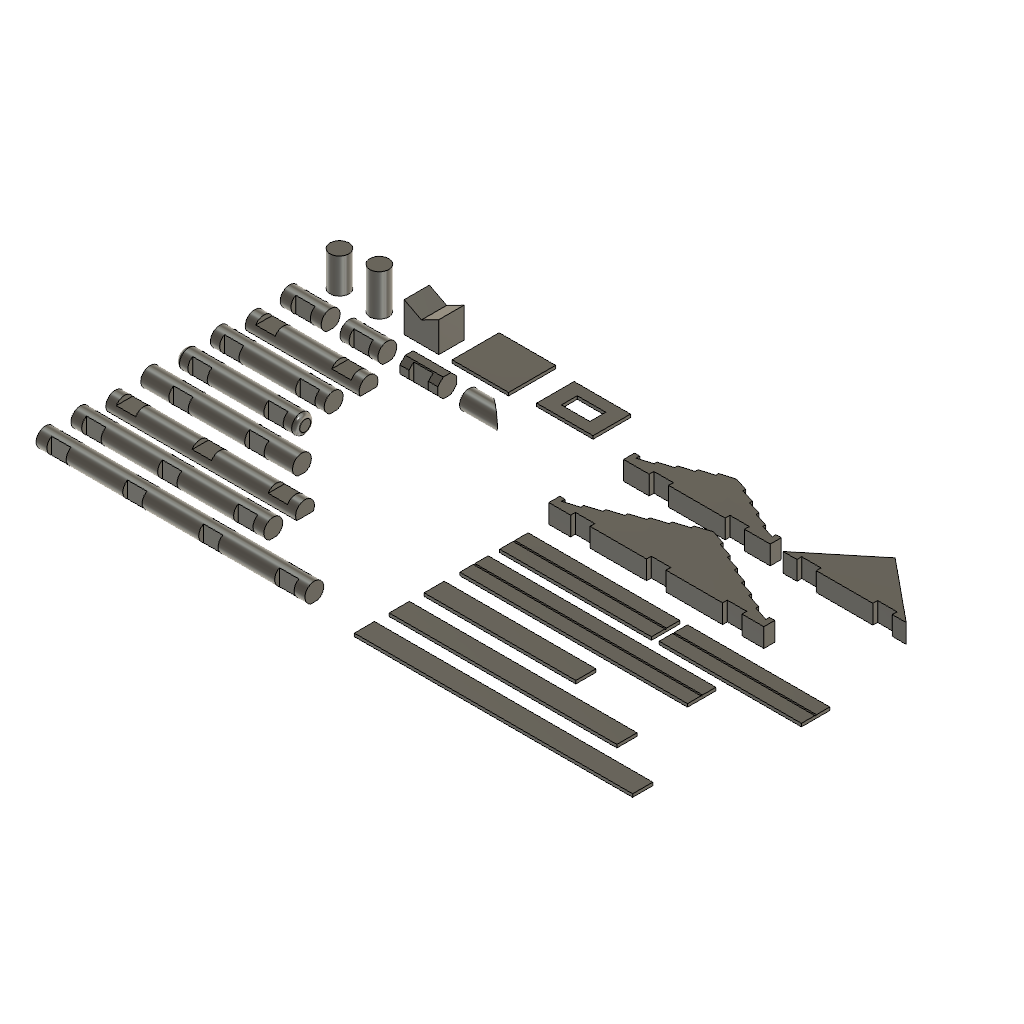
lincoln_logs (Autodesk Fusion 360 design; units mm, degrees)
part number: 2026-11-10-09-19-09-464
part number: 2026-11-10-09-19-09-786
part number: 2026-11-10-09-19-09-864
part number: 2026-11-10-09-19-09-945
part number: 2026-11-10-09-19-10-058
part number: 2026-11-10-09-19-10-167
part number: 2026-11-10-09-19-10-289
part number: 2026-11-10-09-19-10-433
part number: 2026-11-10-09-19-10-590
part number: 2026-11-10-09-19-10-777
part number: 2026-11-10-09-19-10-901
part number: 2026-11-10-09-19-11-031
part number: 2026-11-10-09-19-11-149
part number: 2026-11-10-09-19-11-184
part number: 2026-11-10-09-19-11-255
part number: 2026-11-10-09-19-11-618
part number: 2026-11-10-09-19-12-021
part number: 2026-11-10-09-19-12-238
part number: 2026-11-10-09-19-12-344
part number: 2026-11-10-09-19-12-451
part number: 2026-11-10-09-19-12-561
part number: 2026-11-10-09-19-12-786
part number: 2026-11-10-09-19-13-022
part number: 2026-11-10-09-19-13-284
part number: 2026-11-10-09-19-13-795
part number: 2026-11-10-09-19-13-962
Autodesk Fusion 360 part; units mm, degrees
(part 1 of 2)
sketch "Section" plane through (0, 0, 0) normal (1, 0, 0) x (0, 0, -1) in component "log_1insert_1-5_8"
  circle A0 centre (-8.725, 0) radius 9.525
  line L0 (0, -3.821) -> (0, 3.821)
  dimension "d20" = 8.725
  dimension "d21" = 19.05
  constraint horizontal origin A0.centre
  constraint coincident A0 L0.start
  constraint coincident A0 L0.end
  constraint coincident origin L0
  constraint vertical L0
  measures "d20" horizontal distance of origin A0.centre
  measures "d21" diameter of A0
extrude "Log" add sketch "Section" along normal blind 41.275 contours A0 L0 picked at (-13.348, 0.8095) makes body 1 in component "log_1insert_1-5_8"
sketch "Notch" plane through (0, 0, 0) normal (0, 0, 1) x (1, 0, 0) in component "log_1insert_1-5_8"
  line L0 (10.9125, 4.7625) -> (30.3625, 4.7625)
  line L1 (30.3625, 4.7625) -> (30.3625, 10.525)
  line L2 (30.3625, 10.525) -> (10.9125, 10.525)
  line L3 (10.9125, 10.525) -> (10.9125, 4.7625)
  line L4 (10.9125, -4.7625) -> (30.3625, -4.7625)
  line L5 (30.3625, -4.7625) -> (30.3625, -10.525)
  line L6 (30.3625, -10.525) -> (10.9125, -10.525)
  line L7 (10.9125, -10.525) -> (10.9125, -4.7625)
  dimension "d24" = 10.9125
  dimension "d25" = 4.7625
  dimension "d26" = 30.3625
  dimension "d27" = 10.525
  dimension "d28" = 10.9125
  dimension "d29" = 4.7625
  dimension "d30" = 30.3625
  dimension "d31" = 10.525
  constraint horizontal L0
  constraint vertical L1
  constraint horizontal L2
  constraint vertical L3
  constraint horizontal L4
  constraint vertical L5
  constraint horizontal L6
  constraint vertical L7
  measures "d24" horizontal distance of origin L0.start
  measures "d25" vertical distance of origin L0.start
  measures "d26" horizontal distance of origin L1.end
  measures "d27" vertical distance of origin L1.end
  measures "d28" horizontal distance of origin L4.start
  measures "d29" vertical distance of origin L4.start
  measures "d30" horizontal distance of origin L5.end
  measures "d31" vertical distance of origin L5.end
extrude "Notch cut" cut sketch "Notch" along normal blind 19.05 bodies 1 in component "log_1insert_1-5_8"
pattern_linear "Notch pattern" count 2 spacing 0.001 along (1, 0, 0) count 3 spacing 0 along (1, 0, 0) of "Notch cut" in component "log_1insert_1-5_8"
sketch "Section (2)" plane through (0, 0, 0) normal (1, 0, 0) x (0, 0, -1) in component "log_1insert_1-1_2_round"
  circle A0 centre (-8.725, 0) radius 9.525
  line L0 (0, -3.821) -> (0, 3.821)
  dimension "d42" = 8.725
  dimension "d43" = 19.05
  constraint horizontal origin A0.centre
  constraint coincident A0 L0.start
  constraint coincident A0 L0.end
  constraint coincident origin L0
  constraint vertical L0
  measures "d42" horizontal distance of origin A0.centre
  measures "d43" diameter of A0
extrude "Log'" add sketch "Section (2)" along normal blind 38.1 separate body contours A0 L0 picked at (-13.348, 0.8095) makes body 2 in component "log_1insert_1-1_2_round"
sketch "Notch (2)" plane through (0, 0, 0) normal (0, 0, 1) x (1, 0, 0) in component "log_1insert_1-1_2_round"
  line L0 (9.325, 4.7625) -> (28.775, 4.7625)
  line L1 (28.775, 4.7625) -> (28.775, 10.525)
  line L2 (28.775, 10.525) -> (9.325, 10.525)
  line L3 (9.325, 10.525) -> (9.325, 4.7625)
  line L4 (9.325, -4.7625) -> (28.775, -4.7625)
  line L5 (28.775, -4.7625) -> (28.775, -10.525)
  line L6 (28.775, -10.525) -> (9.325, -10.525)
  line L7 (9.325, -10.525) -> (9.325, -4.7625)
  dimension "d46" = 9.325
  dimension "d47" = 4.7625
  dimension "d48" = 28.775
  dimension "d49" = 10.525
  dimension "d50" = 9.325
  dimension "d51" = 4.7625
  dimension "d52" = 28.775
  dimension "d53" = 10.525
  constraint horizontal L0
  constraint vertical L1
  constraint horizontal L2
  constraint vertical L3
  constraint horizontal L4
  constraint vertical L5
  constraint horizontal L6
  constraint vertical L7
  measures "d46" horizontal distance of origin L0.start
  measures "d47" vertical distance of origin L0.start
  measures "d48" horizontal distance of origin L1.end
  measures "d49" vertical distance of origin L1.end
  measures "d50" horizontal distance of origin L4.start
  measures "d51" vertical distance of origin L4.start
  measures "d52" horizontal distance of origin L5.end
  measures "d53" vertical distance of origin L5.end
extrude "Notch cut'" cut sketch "Notch (2)" along normal blind 19.05 bodies 2 in component "log_1insert_1-1_2_round"
pattern_linear "Notch pattern'" count 2 spacing 0.001 along (1, 0, 0) count 3 spacing 0 along (1, 0, 0) of "Notch cut'" in component "log_1insert_1-1_2_round"
sketch "Section (3)" plane through (0, 0, 0) normal (1, 0, 0) x (0, 0, -1) in component "log_1insert_1-1_2_octagonal"
  line L0 (0, -9.525) -> (0, 9.525)
  line L1 (0, 9.525) -> (-19.05, 9.525)
  line L2 (-19.05, 9.525) -> (-19.05, -9.525)
  line L3 (-19.05, -9.525) -> (0, -9.525)
  dimension "d64" = 9.525
  dimension "d65" = 9.525
  dimension "d66" = 19.05
  constraint vertical L0
  constraint horizontal L1
  constraint vertical L2
  constraint horizontal L3
  constraint vertical origin L0.start
  measures "d64" vertical distance of origin L0.start
  measures "d65" vertical distance of origin L1.end
  measures "d66" horizontal distance of origin L1.end
extrude "Log''" add sketch "Section (3)" along normal blind 38.1 separate body makes body 3 in component "log_1insert_1-1_2_octagonal"
chamfer "Octagon corners" distance 5.5796 angle 45 4 edges at (19.05, -9.525, 19.05) (19.05, 9.525, 19.05) (19.05, 9.525, 0) (19.05, -9.525, 0) tangent chain off on bodies 3 in component "log_1insert_1-1_2_octagonal"
sketch "Notch (3)" plane through (0, 0, 0) normal (0, 0, 1) x (1, 0, 0) in component "log_1insert_1-1_2_octagonal"
  line L0 (9.325, 4.7625) -> (28.775, 4.7625)
  line L1 (28.775, 4.7625) -> (28.775, 10.525)
  line L2 (28.775, 10.525) -> (9.325, 10.525)
  line L3 (9.325, 10.525) -> (9.325, 4.7625)
  line L4 (9.325, -4.7625) -> (28.775, -4.7625)
  line L5 (28.775, -4.7625) -> (28.775, -10.525)
  line L6 (28.775, -10.525) -> (9.325, -10.525)
  line L7 (9.325, -10.525) -> (9.325, -4.7625)
  dimension "d70" = 9.325
  dimension "d71" = 4.7625
  dimension "d72" = 28.775
  dimension "d73" = 10.525
  dimension "d74" = 9.325
  dimension "d75" = 4.7625
  dimension "d76" = 28.775
  dimension "d77" = 10.525
  constraint horizontal L0
  constraint vertical L1
  constraint horizontal L2
  constraint vertical L3
  constraint horizontal L4
  constraint vertical L5
  constraint horizontal L6
  constraint vertical L7
  measures "d70" horizontal distance of origin L0.start
  measures "d71" vertical distance of origin L0.start
  measures "d72" horizontal distance of origin L1.end
  measures "d73" vertical distance of origin L1.end
  measures "d74" horizontal distance of origin L4.start
  measures "d75" vertical distance of origin L4.start
  measures "d76" horizontal distance of origin L5.end
  measures "d77" vertical distance of origin L5.end
extrude "Notch cut''" cut sketch "Notch (3)" along normal blind 19.05 bodies 3 in component "log_1insert_1-1_2_octagonal"
pattern_linear "Notch pattern''" count 2 spacing 0.001 along (1, 0, 0) count 3 spacing 0 along (1, 0, 0) of "Notch cut''" in component "log_1insert_1-1_2_octagonal"
sketch "Section (4)" plane through (0, 0, 0) normal (1, 0, 0) x (0, 0, -1) in component "log_2insert_4-1_2"
  circle A0 centre (-8.725, 0) radius 9.525
  line L0 (0, -3.821) -> (0, 3.821)
  dimension "d88" = 8.725
  dimension "d89" = 19.05
  constraint horizontal origin A0.centre
  constraint coincident A0 L0.start
  constraint coincident A0 L0.end
  constraint coincident origin L0
  constraint vertical L0
  measures "d88" horizontal distance of origin A0.centre
  measures "d89" diameter of A0
extrude "Log'''" add sketch "Section (4)" along normal blind 114.3 separate body contours A0 L0 picked at (-13.348, 0.8095) makes body 4 in component "log_2insert_4-1_2"
sketch "Notch (4)" plane through (0, 0, 0) normal (0, 0, 1) x (1, 0, 0) in component "log_2insert_4-1_2"
  line L0 (9.325, 4.7625) -> (28.775, 4.7625)
  line L1 (28.775, 4.7625) -> (28.775, 10.525)
  line L2 (28.775, 10.525) -> (9.325, 10.525)
  line L3 (9.325, 10.525) -> (9.325, 4.7625)
  line L4 (9.325, -4.7625) -> (28.775, -4.7625)
  line L5 (28.775, -4.7625) -> (28.775, -10.525)
  line L6 (28.775, -10.525) -> (9.325, -10.525)
  line L7 (9.325, -10.525) -> (9.325, -4.7625)
  dimension "d92" = 9.325
  dimension "d93" = 4.7625
  dimension "d94" = 28.775
  dimension "d95" = 10.525
  dimension "d96" = 9.325
  dimension "d97" = 4.7625
  dimension "d98" = 28.775
  dimension "d99" = 10.525
  constraint horizontal L0
  constraint vertical L1
  constraint horizontal L2
  constraint vertical L3
  constraint horizontal L4
  constraint vertical L5
  constraint horizontal L6
  constraint vertical L7
  measures "d92" horizontal distance of origin L0.start
  measures "d93" vertical distance of origin L0.start
  measures "d94" horizontal distance of origin L1.end
  measures "d95" vertical distance of origin L1.end
  measures "d96" horizontal distance of origin L4.start
  measures "d97" vertical distance of origin L4.start
  measures "d98" horizontal distance of origin L5.end
  measures "d99" vertical distance of origin L5.end
extrude "Notch cut'''" cut sketch "Notch (4)" along normal blind 19.05 bodies 4 in component "log_2insert_4-1_2"
pattern_linear "Notch pattern'''" count 2 spacing 76.2 along (1, 0, 0) count 3 spacing 0 along (1, 0, 0) of "Notch cut'''" in component "log_2insert_4-1_2"
sketch "Section (5)" plane through (0, 0, 0) normal (1, 0, 0) x (0, 0, -1) in component "log_2insert_6"
  circle A0 centre (-8.725, 0) radius 9.525
  line L0 (0, -3.821) -> (0, 3.821)
  dimension "d110" = 8.725
  dimension "d111" = 19.05
  constraint horizontal origin A0.centre
  constraint coincident A0 L0.start
  constraint coincident A0 L0.end
  constraint coincident origin L0
  constraint vertical L0
  measures "d110" horizontal distance of origin A0.centre
  measures "d111" diameter of A0
extrude "Log''''" add sketch "Section (5)" along normal blind 152.4 separate body contours A0 L0 picked at (-13.348, 0.8095) makes body 5 in component "log_2insert_6"
sketch "Notch (5)" plane through (0, 0, 0) normal (0, 0, 1) x (1, 0, 0) in component "log_2insert_6"
  line L0 (28.375, 4.7625) -> (47.825, 4.7625)
  line L1 (47.825, 4.7625) -> (47.825, 10.525)
  line L2 (47.825, 10.525) -> (28.375, 10.525)
  line L3 (28.375, 10.525) -> (28.375, 4.7625)
  line L4 (28.375, -4.7625) -> (47.825, -4.7625)
  line L5 (47.825, -4.7625) -> (47.825, -10.525)
  line L6 (47.825, -10.525) -> (28.375, -10.525)
  line L7 (28.375, -10.525) -> (28.375, -4.7625)
  dimension "d114" = 28.375
  dimension "d115" = 4.7625
  dimension "d116" = 47.825
  dimension "d117" = 10.525
  dimension "d118" = 28.375
  dimension "d119" = 4.7625
  dimension "d120" = 47.825
  dimension "d121" = 10.525
  constraint horizontal L0
  constraint vertical L1
  constraint horizontal L2
  constraint vertical L3
  constraint horizontal L4
  constraint vertical L5
  constraint horizontal L6
  constraint vertical L7
  measures "d114" horizontal distance of origin L0.start
  measures "d115" vertical distance of origin L0.start
  measures "d116" horizontal distance of origin L1.end
  measures "d117" vertical distance of origin L1.end
  measures "d118" horizontal distance of origin L4.start
  measures "d119" vertical distance of origin L4.start
  measures "d120" horizontal distance of origin L5.end
  measures "d121" vertical distance of origin L5.end
extrude "Notch cut''''" cut sketch "Notch (5)" along normal blind 19.05 bodies 5 in component "log_2insert_6"
pattern_linear "Notch pattern''''" count 2 spacing 76.2 along (1, 0, 0) count 3 spacing 0 along (1, 0, 0) of "Notch cut''''" in component "log_2insert_6"
sketch "Section (6)" plane through (0, 0, 0) normal (1, 0, 0) x (0, 0, -1) in component "log_3insert_7-5_8"
  circle A0 centre (-8.725, 0) radius 9.525
  line L0 (0, -3.821) -> (0, 3.821)
  dimension "d132" = 8.725
  dimension "d133" = 19.05
  constraint horizontal origin A0.centre
  constraint coincident A0 L0.start
  constraint coincident A0 L0.end
  constraint coincident origin L0
  constraint vertical L0
  measures "d132" horizontal distance of origin A0.centre
  measures "d133" diameter of A0
extrude "Log'''''" add sketch "Section (6)" along normal blind 193.675 separate body contours A0 L0 picked at (-13.348, 0.8095) makes body 6 in component "log_3insert_7-5_8"
sketch "Notch (6)" plane through (0, 0, 0) normal (0, 0, 1) x (1, 0, 0) in component "log_3insert_7-5_8"
  line L0 (10.9125, 4.7625) -> (30.3625, 4.7625)
  line L1 (30.3625, 4.7625) -> (30.3625, 10.525)
  line L2 (30.3625, 10.525) -> (10.9125, 10.525)
  line L3 (10.9125, 10.525) -> (10.9125, 4.7625)
  line L4 (10.9125, -4.7625) -> (30.3625, -4.7625)
  line L5 (30.3625, -4.7625) -> (30.3625, -10.525)
  line L6 (30.3625, -10.525) -> (10.9125, -10.525)
  line L7 (10.9125, -10.525) -> (10.9125, -4.7625)
  dimension "d136" = 10.9125
  dimension "d137" = 4.7625
  dimension "d138" = 30.3625
  dimension "d139" = 10.525
  dimension "d140" = 10.9125
  dimension "d141" = 4.7625
  dimension "d142" = 30.3625
  dimension "d143" = 10.525
  constraint horizontal L0
  constraint vertical L1
  constraint horizontal L2
  constraint vertical L3
  constraint horizontal L4
  constraint vertical L5
  constraint horizontal L6
  constraint vertical L7
  measures "d136" horizontal distance of origin L0.start
  measures "d137" vertical distance of origin L0.start
  measures "d138" horizontal distance of origin L1.end
  measures "d139" vertical distance of origin L1.end
  measures "d140" horizontal distance of origin L4.start
  measures "d141" vertical distance of origin L4.start
  measures "d142" horizontal distance of origin L5.end
  measures "d143" vertical distance of origin L5.end
extrude "Notch cut'''''" cut sketch "Notch (6)" along normal blind 19.05 bodies 6 in component "log_3insert_7-5_8"
pattern_linear "Notch pattern'''''" count 3 spacing 76.2 along (1, 0, 0) count 3 spacing 0 along (1, 0, 0) of "Notch cut'''''" in component "log_3insert_7-5_8"
sketch "Section (7)" plane through (0, 0, 0) normal (1, 0, 0) x (0, 0, -1) in component "log_4insert_10-5_8"
  circle A0 centre (-8.725, 0) radius 9.525
  line L0 (0, -3.821) -> (0, 3.821)
  dimension "d154" = 8.725
  dimension "d155" = 19.05
  constraint horizontal origin A0.centre
  constraint coincident A0 L0.start
  constraint coincident A0 L0.end
  constraint coincident origin L0
  constraint vertical L0
  measures "d154" horizontal distance of origin A0.centre
  measures "d155" diameter of A0
extrude "Log''''''" add sketch "Section (7)" along normal blind 269.875 separate body contours A0 L0 picked at (-13.348, 0.8095) makes body 7 in component "log_4insert_10-5_8"
sketch "Notch (7)" plane through (0, 0, 0) normal (0, 0, 1) x (1, 0, 0) in component "log_4insert_10-5_8"
  line L0 (10.9125, 4.7625) -> (30.3625, 4.7625)
  line L1 (30.3625, 4.7625) -> (30.3625, 10.525)
  line L2 (30.3625, 10.525) -> (10.9125, 10.525)
  line L3 (10.9125, 10.525) -> (10.9125, 4.7625)
  line L4 (10.9125, -4.7625) -> (30.3625, -4.7625)
  line L5 (30.3625, -4.7625) -> (30.3625, -10.525)
  line L6 (30.3625, -10.525) -> (10.9125, -10.525)
  line L7 (10.9125, -10.525) -> (10.9125, -4.7625)
  dimension "d158" = 10.9125
  dimension "d159" = 4.7625
  dimension "d160" = 30.3625
  dimension "d161" = 10.525
  dimension "d162" = 10.9125
  dimension "d163" = 4.7625
  dimension "d164" = 30.3625
  dimension "d165" = 10.525
  constraint horizontal L0
  constraint vertical L1
  constraint horizontal L2
  constraint vertical L3
  constraint horizontal L4
  constraint vertical L5
  constraint horizontal L6
  constraint vertical L7
  measures "d158" horizontal distance of origin L0.start
  measures "d159" vertical distance of origin L0.start
  measures "d160" horizontal distance of origin L1.end
  measures "d161" vertical distance of origin L1.end
  measures "d162" horizontal distance of origin L4.start
  measures "d163" vertical distance of origin L4.start
  measures "d164" horizontal distance of origin L5.end
  measures "d165" vertical distance of origin L5.end
extrude "Notch cut''''''" cut sketch "Notch (7)" along normal blind 19.05 bodies 7 in component "log_4insert_10-5_8"
pattern_linear "Notch pattern''''''" count 4 spacing 76.2 along (1, 0, 0) count 3 spacing 0 along (1, 0, 0) of "Notch cut''''''" in component "log_4insert_10-5_8"
sketch "Section (8)" plane through (0, 0, 0) normal (1, 0, 0) x (0, 0, -1) in component "beveled_end_4-3_4"
  circle A0 centre (-8.725, 0) radius 9.525
  line L0 (0, -3.821) -> (0, 3.821)
  dimension "d176" = 8.725
  dimension "d177" = 19.05
  constraint horizontal origin A0.centre
  constraint coincident A0 L0.start
  constraint coincident A0 L0.end
  constraint coincident origin L0
  constraint vertical L0
  measures "d176" horizontal distance of origin A0.centre
  measures "d177" diameter of A0
extrude "Log'''''''" add sketch "Section (8)" along normal blind 120.65 separate body makes body 8 in component "beveled_end_4-3_4"
fillet "Rounded ends" radius 4 2 edges at (120.65, -3.4444, 17.6054) (0, -3.4444, 17.6054) on bodies 8 in component "beveled_end_4-3_4"
extrude "Printing flat" cut sketch "Section (8)" along normal blind 120.65 contours A0 L0 picked at (0.1472, 0.8627) bodies 8 in component "beveled_end_4-3_4"
sketch "Notch (8)" plane through (0, 0, 0) normal (0, 0, 1) x (1, 0, 0) in component "beveled_end_4-3_4"
  line L0 (12.5, 4.7625) -> (31.95, 4.7625)
  line L1 (31.95, 4.7625) -> (31.95, 10.525)
  line L2 (31.95, 10.525) -> (12.5, 10.525)
  line L3 (12.5, 10.525) -> (12.5, 4.7625)
  line L4 (12.5, -4.7625) -> (31.95, -4.7625)
  line L5 (31.95, -4.7625) -> (31.95, -10.525)
  line L6 (31.95, -10.525) -> (12.5, -10.525)
  line L7 (12.5, -10.525) -> (12.5, -4.7625)
  dimension "d185" = 12.5
  dimension "d186" = 4.7625
  dimension "d187" = 31.95
  dimension "d188" = 10.525
  dimension "d189" = 12.5
  dimension "d190" = 4.7625
  dimension "d191" = 31.95
  dimension "d192" = 10.525
  constraint horizontal L0
  constraint vertical L1
  constraint horizontal L2
  constraint vertical L3
  constraint horizontal L4
  constraint vertical L5
  constraint horizontal L6
  constraint vertical L7
  measures "d185" horizontal distance of origin L0.start
  measures "d186" vertical distance of origin L0.start
  measures "d187" horizontal distance of origin L1.end
  measures "d188" vertical distance of origin L1.end
  measures "d189" horizontal distance of origin L4.start
  measures "d190" vertical distance of origin L4.start
  measures "d191" horizontal distance of origin L5.end
  measures "d192" vertical distance of origin L5.end
extrude "Notch cut'''''''" cut sketch "Notch (8)" along normal blind 19.05 bodies 8 in component "beveled_end_4-3_4"
pattern_linear "Notch pattern'''''''" count 2 spacing 76.2 along (1, 0, 0) count 3 spacing 0 along (1, 0, 0) of "Notch cut'''''''" in component "beveled_end_4-3_4"
sketch "Section (9)" plane through (0, 0, 0) normal (1, 0, 0) x (0, 0, -1) in component "half_log_4-1_2"
  circle A0 centre (-4.7625, 0) radius 9.525
  line L0 (0, -8.2489) -> (0, 8.2489)
  dimension "d203" = 4.7625
  dimension "d204" = 19.05
  constraint horizontal origin A0.centre
  constraint coincident A0 L0.start
  constraint coincident A0 L0.end
  constraint coincident origin L0
  constraint vertical L0
  measures "d203" horizontal distance of origin A0.centre
  measures "d204" diameter of A0
extrude "Log''''''''" add sketch "Section (9)" along normal blind 114.3 separate body contours A0 L0 picked at (-7.0899, 2.1595) makes body 9 in component "half_log_4-1_2"
sketch "Notch (9)" plane through (0, 0, 0) normal (0, 1, 0) x (1, 0, 0) in component "half_log_4-1_2"
  line L0 (9.325, -9.525) -> (28.775, -9.525)
  line L1 (28.775, -9.525) -> (28.775, -15.2875)
  line L2 (28.775, -15.2875) -> (9.325, -15.2875)
  line L3 (9.325, -15.2875) -> (9.325, -9.525)
  dimension "d207" = 9.325
  dimension "d208" = 9.525
  dimension "d209" = 28.775
  dimension "d210" = 15.2875
  constraint horizontal L0
  constraint vertical L1
  constraint horizontal L2
  constraint vertical L3
  measures "d207" horizontal distance of origin L0.start
  measures "d208" vertical distance of origin L0.start
  measures "d209" horizontal distance of origin L1.end
  measures "d210" vertical distance of origin L1.end
extrude "Notch cut''''''''" cut sketch "Notch (9)" along normal mid plane 21.05 bodies 9 in component "half_log_4-1_2"
pattern_linear "Notch pattern''''''''" count 2 spacing 76.2 along (1, 0, 0) count 3 spacing 0 along (1, 0, 0) of "Notch cut''''''''" in component "half_log_4-1_2"
sketch "Section (10)" plane through (0, 0, 0) normal (1, 0, 0) x (0, 0, -1) in component "half_log_7-1_2"
  circle A0 centre (-4.7625, 0) radius 9.525
  line L0 (0, -8.2489) -> (0, 8.2489)
  dimension "d221" = 4.7625
  dimension "d222" = 19.05
  constraint horizontal origin A0.centre
  constraint coincident A0 L0.start
  constraint coincident A0 L0.end
  constraint coincident origin L0
  constraint vertical L0
  measures "d221" horizontal distance of origin A0.centre
  measures "d222" diameter of A0
extrude "Log'''''''''" add sketch "Section (10)" along normal blind 190.5 separate body contours A0 L0 picked at (-7.0899, 2.1595) makes body 10 in component "half_log_7-1_2"
sketch "Notch (10)" plane through (0, 0, 0) normal (0, 1, 0) x (1, 0, 0) in component "half_log_7-1_2"
  line L0 (9.325, -9.525) -> (28.775, -9.525)
  line L1 (28.775, -9.525) -> (28.775, -15.2875)
  line L2 (28.775, -15.2875) -> (9.325, -15.2875)
  line L3 (9.325, -15.2875) -> (9.325, -9.525)
  dimension "d225" = 9.325
  dimension "d226" = 9.525
  dimension "d227" = 28.775
  dimension "d228" = 15.2875
  constraint horizontal L0
  constraint vertical L1
  constraint horizontal L2
  constraint vertical L3
  measures "d225" horizontal distance of origin L0.start
  measures "d226" vertical distance of origin L0.start
  measures "d227" horizontal distance of origin L1.end
  measures "d228" vertical distance of origin L1.end
extrude "Notch cut'''''''''" cut sketch "Notch (10)" along normal mid plane 21.05 bodies 10 in component "half_log_7-1_2"
pattern_linear "Notch pattern'''''''''" count 3 spacing 76.2 along (1, 0, 0) count 3 spacing 0 along (1, 0, 0) of "Notch cut'''''''''" in component "half_log_7-1_2"
sketch "Section (11)" plane through (0, 0, 0) normal (1, 0, 0) x (0, 0, -1) in component "beveled_end_1-1_2"
  circle A0 centre (-8.725, 0) radius 9.525
  line L0 (0, -3.821) -> (0, 3.821)
  dimension "d237" = 8.725
  dimension "d238" = 19.05
  constraint horizontal origin A0.centre
  constraint coincident A0 L0.start
  constraint coincident A0 L0.end
  constraint coincident origin L0
  constraint vertical L0
  measures "d237" horizontal distance of origin A0.centre
  measures "d238" diameter of A0
extrude "Log''''''''''" add sketch "Section (11)" along normal blind 38.1 separate body contours A0 L0 picked at (-13.348, 0.8095) makes body 11 in component "beveled_end_1-1_2"
sketch "Slant" plane through (0, 0, 0) normal (0, 0, 1) x (1, 0, 0) in component "beveled_end_1-1_2"
  line L0 (38.1, -9.525) -> (38.1, 9.525)
  line L1 (38.1, 9.525) -> (14.5752, 9.525)
  line L2 (14.5752, 9.525) -> (38.1, -9.525)
  dimension "d241" = 38.1
  dimension "d242" = 9.525
  dimension "d243" = 9.525
  dimension "d244" = 14.5752
  constraint vertical L0.start L0.end
  constraint horizontal L0.end L1.end
  measures "d241" horizontal distance of origin L0.start
  measures "d242" vertical distance of origin L0.start
  measures "d243" vertical distance of origin L0.end
  measures "d244" horizontal distance of origin L1.end
extrude "Slanted end" cut sketch "Slant" along normal blind 19.05 bodies 11 in component "beveled_end_1-1_2"
sketch "Section (12)" plane through (0, 0, 0) normal (0, 0, 1) x (1, 0, 0) in component "solid_log_1-3_8"
  circle A0 centre (0, 0) radius 9.525
  dimension "d248" = 19.05
  measures "d248" diameter of A0
extrude "Log'''''''''''" add sketch "Section (12)" along normal blind 34.925 separate body makes body 12 in component "solid_log_1-3_8"
sketch "Section (13)" plane through (0, 0, 0) normal (0, 0, 1) x (1, 0, 0) in component "solid_log_1-5_8"
  circle A0 centre (0, 0) radius 9.525
  dimension "d252" = 19.05
  measures "d252" diameter of A0
extrude "Log''''''''''''" add sketch "Section (13)" along normal blind 41.275 separate body makes body 13 in component "solid_log_1-5_8"
sketch "Half profile" plane through (0, 0, 0) normal (0, 0, 1) x (1, 0, 0) in component "gable_plastic_8-1_2"
  line L0 (0, 0) -> (107.95, 0)
  line L1 (107.95, 0) -> (107.95, 60.05)
  line L2 (107.95, 60.05) -> (5.4, 7.5)
  line L3 (5.4, 7.5) -> (5.4, 11.1)
  line L4 (5.4, 11.1) -> (0, 11.1)
  line L5 (0, 11.1) -> (0, 0)
  dimension "d282" = 107.95
  dimension "d283" = 60.05
  dimension "d284" = 5.4
  dimension "d285" = 7.5
  dimension "d286" = 11.1
  constraint coincident L0.start L5.end
  constraint horizontal L0.start L0.end
  constraint vertical L0.end L1.end
  constraint vertical L2.end L3.end
  constraint vertical L0.start L4.end
  constraint horizontal L3.end L4.end
  measures "d282" horizontal distance of L0.start L0.end
  measures "d283" vertical distance of L0.start L1.end
  measures "d284" horizontal distance of L0.start L2.end
  measures "d285" vertical distance of L0.start L2.end
  measures "d286" vertical distance of L0.start L3.end
extrude "Half gable" add sketch "Half profile" along normal blind 19.05 separate body makes body 14 in component "gable_plastic_8-1_2"
sketch "Step" plane through (0, 0, 0) normal (0, 0, 1) x (1, 0, 0) in component "gable_plastic_8-1_2"
  line L0 (5.4, 7.5) -> (20.05, 15.0071)
  line L1 (20.05, 15.0071) -> (20.05, 12.1071)
  line L2 (20.05, 12.1071) -> (5.4, 7.5)
  dimension "d289" = 5.4
  dimension "d290" = 7.5
  dimension "d291" = 20.05
  dimension "d292" = 15.0071
  dimension "d293" = 12.1071
  constraint vertical L0.end L1.end
  measures "d289" horizontal distance of origin L0.start
  measures "d290" vertical distance of origin L0.start
  measures "d291" horizontal distance of origin L0.end
  measures "d292" vertical distance of origin L0.end
  measures "d293" vertical distance of origin L1.end
extrude "Step cut" cut sketch "Step" along normal blind 19.05 bodies 14 in component "gable_plastic_8-1_2"
pattern_linear "Step pattern" count 7 spacing 16.4615 along (0.889957, 0.456044, 0) count 3 spacing 0 along (0.889957, 0.456044, 0) of "Step cut" in component "gable_plastic_8-1_2"
ref_plane "WorkPlane1" through (107.95, 0, 0) normal (1, 0, 0) x (0, 1, 0) in component "gable_plastic_8-1_2"
mirror "Mirror half" about plane through (107.95, 0, 0) normal (1, 0, 0) of bodies 14 merged in component "gable_plastic_8-1_2"
sketch "Notch (11)" plane through (0, 0, 0) normal (0, 0, 1) x (1, 0, 0) in component "gable_plastic_8-1_2"
  line L0 (22.025, -1) -> (41.475, -1)
  line L1 (41.475, -1) -> (41.475, 4.7625)
  line L2 (41.475, 4.7625) -> (22.025, 4.7625)
  line L3 (22.025, 4.7625) -> (22.025, -1)
  dimension "d304" = 22.025
  dimension "d305" = 1
  dimension "d306" = 41.475
  dimension "d307" = 4.7625
  constraint horizontal L0
  constraint vertical L1
  constraint horizontal L2
  constraint vertical L3
  measures "d304" horizontal distance of origin L0.start
  measures "d305" vertical distance of origin L0.start
  measures "d306" horizontal distance of origin L1.end
  measures "d307" vertical distance of origin L1.end
extrude "Notch cut''''''''''" cut sketch "Notch (11)" along normal blind 19.05 bodies 14 in component "gable_plastic_8-1_2"
pattern_linear "Notch pattern''''''''''" count 3 spacing 76.2 along (1, 0, 0) count 3 spacing 0 along (1, 0, 0) of "Notch cut''''''''''" in component "gable_plastic_8-1_2"
sketch "Half profile (2)" plane through (0, 0, 0) normal (0, 0, 1) x (1, 0, 0) in component "gable_plastic_small_2notch"
  line L0 (0, 0) -> (73.66, 0)
  line L1 (73.66, 0) -> (73.66, 42.4787)
  line L2 (73.66, 42.4787) -> (5.4, 7.5)
  line L3 (5.4, 7.5) -> (5.4, 11.1)
  line L4 (5.4, 11.1) -> (0, 11.1)
  line L5 (0, 11.1) -> (0, 0)
  dimension "d314" = 73.66
  dimension "d315" = 42.4787
  dimension "d316" = 5.4
  dimension "d317" = 7.5
  dimension "d318" = 11.1
  constraint coincident L0.start L5.end
  constraint horizontal L0.start L0.end
  constraint vertical L0.end L1.end
  constraint vertical L2.end L3.end
  constraint vertical L0.start L4.end
  constraint horizontal L3.end L4.end
  measures "d314" horizontal distance of L0.start L0.end
  measures "d315" vertical distance of L0.start L1.end
  measures "d316" horizontal distance of L0.start L2.end
  measures "d317" vertical distance of L0.start L2.end
  measures "d318" vertical distance of L0.start L3.end
extrude "Half gable'" add sketch "Half profile (2)" along normal blind 19.05 separate body makes body 15 in component "gable_plastic_small_2notch"
sketch "Step (2)" plane through (0, 0, 0) normal (0, 0, 1) x (1, 0, 0) in component "gable_plastic_small_2notch"
  line L0 (5.4, 7.5) -> (19.052, 14.4957)
  line L1 (19.052, 14.4957) -> (19.052, 11.5957)
  line L2 (19.052, 11.5957) -> (5.4, 7.5)
  dimension "d321" = 5.4
  dimension "d322" = 7.5
  dimension "d323" = 19.052
  dimension "d324" = 14.4957
  dimension "d325" = 11.5957
  constraint vertical L0.end L1.end
  measures "d321" horizontal distance of origin L0.start
  measures "d322" vertical distance of origin L0.start
  measures "d323" horizontal distance of origin L0.end
  measures "d324" vertical distance of origin L0.end
  measures "d325" vertical distance of origin L1.end
extrude "Step cut'" cut sketch "Step (2)" along normal blind 19.05 bodies 15 in component "gable_plastic_small_2notch"
pattern_linear "Step pattern'" count 5 spacing 15.3401 along (0.889957, 0.456044, 0) count 3 spacing 0 along (0.889957, 0.456044, 0) of "Step cut'" in component "gable_plastic_small_2notch"
ref_plane "WorkPlane1" through (73.66, 0, 0) normal (1, 0, 0) x (0, 1, 0) in component "gable_plastic_small_2notch"
mirror "Mirror half'" about plane through (73.66, 0, 0) normal (1, 0, 0) of bodies 15 merged in component "gable_plastic_small_2notch"
sketch "Notch (12)" plane through (0, 0, 0) normal (0, 0, 1) x (1, 0, 0) in component "gable_plastic_small_2notch"
  line L0 (25.835, -1) -> (45.285, -1)
  line L1 (45.285, -1) -> (45.285, 4.7625)
  line L2 (45.285, 4.7625) -> (25.835, 4.7625)
  line L3 (25.835, 4.7625) -> (25.835, -1)
  dimension "d336" = 25.835
  dimension "d337" = 1
  dimension "d338" = 45.285
  dimension "d339" = 4.7625
  constraint horizontal L0
  constraint vertical L1
  constraint horizontal L2
  constraint vertical L3
  measures "d336" horizontal distance of origin L0.start
  measures "d337" vertical distance of origin L0.start
  measures "d338" horizontal distance of origin L1.end
  measures "d339" vertical distance of origin L1.end
extrude "Notch cut'''''''''''" cut sketch "Notch (12)" along normal blind 19.05 bodies 15 in component "gable_plastic_small_2notch"
pattern_linear "Notch pattern'''''''''''" count 2 spacing 76.2 along (1, 0, 0) count 3 spacing 0 along (1, 0, 0) of "Notch cut'''''''''''" in component "gable_plastic_small_2notch"
sketch "Profile" plane through (0, 0, 0) normal (0, 0, 1) x (1, 0, 0) in component "gable_wood_triangle_4x2"
  line L0 (0, 0) -> (123.825, 0)
  line L1 (123.825, 0) -> (61.9125, 50.8)
  line L2 (61.9125, 50.8) -> (0, 0)
  dimension "d351" = 123.825
  dimension "d352" = 61.9125
  dimension "d353" = 50.8
  constraint coincident L0.start L2.end
  constraint horizontal L0.start L0.end
  measures "d351" horizontal distance of L0.start L0.end
  measures "d352" horizontal distance of L0.start L1.end
  measures "d353" vertical distance of L0.start L1.end
extrude "Gable" add sketch "Profile" along normal blind 19.05 separate body makes body 16 in component "gable_wood_triangle_4x2"
sketch "Notch (13)" plane through (0, 0, 0) normal (0, 0, 1) x (1, 0, 0) in component "gable_wood_triangle_4x2"
  line L0 (14.0875, -1) -> (33.5375, -1)
  line L1 (33.5375, -1) -> (33.5375, 4.7625)
  line L2 (33.5375, 4.7625) -> (14.0875, 4.7625)
  line L3 (14.0875, 4.7625) -> (14.0875, -1)
  dimension "d356" = 14.0875
  dimension "d357" = 1
  dimension "d358" = 33.5375
  dimension "d359" = 4.7625
  constraint horizontal L0
  constraint vertical L1
  constraint horizontal L2
  constraint vertical L3
  measures "d356" horizontal distance of origin L0.start
  measures "d357" vertical distance of origin L0.start
  measures "d358" horizontal distance of origin L1.end
  measures "d359" vertical distance of origin L1.end
extrude "Notch cut''''''''''''" cut sketch "Notch (13)" along normal blind 19.05 bodies 16 in component "gable_wood_triangle_4x2"
pattern_linear "Notch pattern''''''''''''" count 2 spacing 76.2 along (1, 0, 0) count 3 spacing 0 along (1, 0, 0) of "Notch cut''''''''''''" in component "gable_wood_triangle_4x2"
sketch "Outline" plane through (0, 0, 0) normal (0, 0, 1) x (1, 0, 0)
  line L0 (0, -10.16) -> (152.4, -10.16)
  line L1 (152.4, -10.16) -> (152.4, 10.16)
  line L2 (152.4, 10.16) -> (0, 10.16)
  line L3 (0, 10.16) -> (0, -10.16)
  dimension "d367" = 10.16
  dimension "d368" = 152.4
  dimension "d369" = 10.16
  constraint horizontal L0
  constraint vertical L1
  constraint horizontal L2
  constraint vertical L3
  constraint vertical origin L0.start
  measures "d367" vertical distance of origin L0.start
  measures "d368" horizontal distance of origin L1.end
  measures "d369" vertical distance of origin L1.end
extrude "Board" add sketch "Outline" along normal blind 3.175 separate body makes body 17
sketch "Outline (2)" plane through (0, 0, 0) normal (0, 0, 1) x (1, 0, 0) in component "shingle_flat_9"
  line L0 (0, -10.16) -> (228.6, -10.16)
  line L1 (228.6, -10.16) -> (228.6, 10.16)
  line L2 (228.6, 10.16) -> (0, 10.16)
  line L3 (0, 10.16) -> (0, -10.16)
  dimension "d373" = 10.16
  dimension "d374" = 228.6
  dimension "d375" = 10.16
  constraint horizontal L0
  constraint vertical L1
  constraint horizontal L2
  constraint vertical L3
  constraint vertical origin L0.start
  measures "d373" vertical distance of origin L0.start
  measures "d374" horizontal distance of origin L1.end
  measures "d375" vertical distance of origin L1.end
extrude "Board'" add sketch "Outline (2)" along normal blind 3.175 separate body makes body 18 in component "shingle_flat_9"
sketch "Outline (3)" plane through (0, 0, 0) normal (0, 0, 1) x (1, 0, 0) in component "shingle_flat_11"
  line L0 (0, -10.16) -> (279.4, -10.16)
  line L1 (279.4, -10.16) -> (279.4, 10.16)
  line L2 (279.4, 10.16) -> (0, 10.16)
  line L3 (0, 10.16) -> (0, -10.16)
  dimension "d379" = 10.16
  dimension "d380" = 279.4
  dimension "d381" = 10.16
  constraint horizontal L0
  constraint vertical L1
  constraint horizontal L2
  constraint vertical L3
  constraint vertical origin L0.start
  measures "d379" vertical distance of origin L0.start
  measures "d380" horizontal distance of origin L1.end
  measures "d381" vertical distance of origin L1.end
extrude "Board''" add sketch "Outline (3)" along normal blind 3.175 separate body makes body 19 in component "shingle_flat_11"
sketch "Outline (4)" plane through (0, 0, 0) normal (0, 0, 1) x (1, 0, 0) in component "shingle_ridge_5-5_8"
  line L0 (0, -14.2875) -> (142.875, -14.2875)
  line L1 (142.875, -14.2875) -> (142.875, 14.2875)
  line L2 (142.875, 14.2875) -> (0, 14.2875)
  line L3 (0, 14.2875) -> (0, -14.2875)
  dimension "d385" = 14.2875
  dimension "d386" = 142.875
  dimension "d387" = 14.2875
  constraint horizontal L0
  constraint vertical L1
  constraint horizontal L2
  constraint vertical L3
  constraint vertical origin L0.start
  measures "d385" vertical distance of origin L0.start
  measures "d386" horizontal distance of origin L1.end
  measures "d387" vertical distance of origin L1.end
extrude "Board'''" add sketch "Outline (4)" along normal blind 3.175 separate body makes body 20 in component "shingle_ridge_5-5_8"
sketch "Groove" plane through (0, 0, 0) normal (1, 0, 0) x (0, 0, -1) in component "shingle_ridge_5-5_8"
  line L0 (-3.175, -0.8) -> (-3.175, 0.8)
  line L1 (-3.175, 0.8) -> (-2.375, 0)
  line L2 (-2.375, 0) -> (-3.175, -0.8)
  dimension "d390" = 0.8
  dimension "d391" = 3.175
  dimension "d392" = 0.8
  dimension "d393" = 2.375
  constraint vertical L0.start L0.end
  constraint horizontal origin L1.end
  measures "d390" vertical distance of origin L0.start
  measures "d391" horizontal distance of origin L0.start
  measures "d392" vertical distance of origin L0.end
  measures "d393" horizontal distance of origin L1.end
extrude "Groove (1)" cut sketch "Groove" along normal blind 142.875 bodies 20 in component "shingle_ridge_5-5_8"
sketch "Outline (5)" plane through (0, 0, 0) normal (0, 0, 1) x (1, 0, 0) in component "shingle_ridge_6"
  line L0 (0, -14.2875) -> (152.4, -14.2875)
  line L1 (152.4, -14.2875) -> (152.4, 14.2875)
  line L2 (152.4, 14.2875) -> (0, 14.2875)
  line L3 (0, 14.2875) -> (0, -14.2875)
  dimension "d397" = 14.2875
  dimension "d398" = 152.4
  dimension "d399" = 14.2875
  constraint horizontal L0
  constraint vertical L1
  constraint horizontal L2
  constraint vertical L3
  constraint vertical origin L0.start
  measures "d397" vertical distance of origin L0.start
  measures "d398" horizontal distance of origin L1.end
  measures "d399" vertical distance of origin L1.end
extrude "Board''''" add sketch "Outline (5)" along normal blind 3.175 separate body makes body 21 in component "shingle_ridge_6"
sketch "Groove (2)" plane through (0, 0, 0) normal (1, 0, 0) x (0, 0, -1) in component "shingle_ridge_6"
  line L0 (-3.175, -0.8) -> (-3.175, 0.8)
  line L1 (-3.175, 0.8) -> (-2.375, 0)
  line L2 (-2.375, 0) -> (-3.175, -0.8)
  dimension "d402" = 0.8
  dimension "d403" = 3.175
  dimension "d404" = 0.8
  dimension "d405" = 2.375
  constraint vertical L0.start L0.end
  constraint horizontal origin L1.end
  measures "d402" vertical distance of origin L0.start
  measures "d403" horizontal distance of origin L0.start
  measures "d404" vertical distance of origin L0.end
  measures "d405" horizontal distance of origin L1.end
extrude "Groove (1)'" cut sketch "Groove (2)" along normal blind 152.4 bodies 21 in component "shingle_ridge_6"
sketch "Outline (6)" plane through (0, 0, 0) normal (0, 0, 1) x (1, 0, 0) in component "shingle_ridge_9"
  line L0 (0, -14.2875) -> (228.6, -14.2875)
  line L1 (228.6, -14.2875) -> (228.6, 14.2875)
  line L2 (228.6, 14.2875) -> (0, 14.2875)
  line L3 (0, 14.2875) -> (0, -14.2875)
  dimension "d409" = 14.2875
  dimension "d410" = 228.6
  dimension "d411" = 14.2875
  constraint horizontal L0
  constraint vertical L1
  constraint horizontal L2
  constraint vertical L3
  constraint vertical origin L0.start
  measures "d409" vertical distance of origin L0.start
  measures "d410" horizontal distance of origin L1.end
  measures "d411" vertical distance of origin L1.end
extrude "Board'''''" add sketch "Outline (6)" along normal blind 3.175 separate body makes body 22 in component "shingle_ridge_9"
sketch "Groove (3)" plane through (0, 0, 0) normal (1, 0, 0) x (0, 0, -1) in component "shingle_ridge_9"
  line L0 (-3.175, -0.8) -> (-3.175, 0.8)
  line L1 (-3.175, 0.8) -> (-2.375, 0)
  line L2 (-2.375, 0) -> (-3.175, -0.8)
  dimension "d414" = 0.8
  dimension "d415" = 3.175
  dimension "d416" = 0.8
  dimension "d417" = 2.375
  constraint vertical L0.start L0.end
  constraint horizontal origin L1.end
  measures "d414" vertical distance of origin L0.start
  measures "d415" horizontal distance of origin L0.start
  measures "d416" vertical distance of origin L0.end
  measures "d417" horizontal distance of origin L1.end
extrude "Groove (1)''" cut sketch "Groove (3)" along normal blind 228.6 bodies 22 in component "shingle_ridge_9"
sketch "Outline (7)" plane through (0, 0, 0) normal (0, 0, 1) x (1, 0, 0) in component "chimney"
  line L0 (-17.4625, -12.7) -> (17.4625, -12.7)
  line L1 (17.4625, -12.7) -> (17.4625, 12.7)
  line L2 (17.4625, 12.7) -> (-17.4625, 12.7)
  line L3 (-17.4625, 12.7) -> (-17.4625, -12.7)
  dimension "d426" = 17.4625
  dimension "d427" = 12.7
  dimension "d428" = 17.4625
  dimension "d429" = 12.7
  constraint horizontal L0
  constraint vertical L1
  constraint horizontal L2
  constraint vertical L3
  measures "d426" horizontal distance of origin L0.start
  measures "d427" vertical distance of origin L0.start
  measures "d428" horizontal distance of origin L1.end
  measures "d429" vertical distance of origin L1.end
extrude "Block" add sketch "Outline (7)" along normal blind 30.48 separate body makes body 23 in component "chimney"
sketch "Pocket" plane through (0, 0, 0) normal (0, 0, 1) x (1, 0, 0) in component "chimney"
  line L0 (-14.4145, -9.652) -> (14.4145, -9.652)
  line L1 (14.4145, -9.652) -> (14.4145, 9.652)
  line L2 (14.4145, 9.652) -> (-14.4145, 9.652)
  line L3 (-14.4145, 9.652) -> (-14.4145, -9.652)
  dimension "d432" = 14.4145
  dimension "d433" = 9.652
  dimension "d434" = 14.4145
  dimension "d435" = 9.652
  constraint horizontal L0
  constraint vertical L1
  constraint horizontal L2
  constraint vertical L3
  measures "d432" horizontal distance of origin L0.start
  measures "d433" vertical distance of origin L0.start
  measures "d434" horizontal distance of origin L1.end
  measures "d435" vertical distance of origin L1.end
extrude "Open top" cut sketch "Pocket" along normal blind 12.7 bodies 23 in component "chimney"
sketch "Ridge V" plane through (0, 0, 0) normal (0, 1, 0) x (1, 0, 0) in component "chimney"
  line L0 (-17.4625, -30.48) -> (17.4625, -30.48)
  line L1 (17.4625, -30.48) -> (0, -21.5316)
  line L2 (0, -21.5316) -> (-17.4625, -30.48)
  dimension "d438" = 17.4625
  dimension "d439" = 30.48
  dimension "d440" = 17.4625
  dimension "d441" = 21.5316
  constraint horizontal L0.start L0.end
  constraint vertical origin L1.end
  measures "d438" horizontal distance of origin L0.start
  measures "d439" vertical distance of origin L0.start
  measures "d440" horizontal distance of origin L0.end
  measures "d441" vertical distance of origin L1.end
extrude "Ridge V cut" cut sketch "Ridge V" along normal mid plane 27.4 bodies 23 in component "chimney"
sketch "Outline (8)" plane through (0, 0, 0) normal (0, 0, 1) x (1, 0, 0) in component "extra_door"
  line L0 (-28.375, -23.6125) -> (28.375, -23.6125)
  line L1 (28.375, -23.6125) -> (28.375, 23.6125)
  line L2 (28.375, 23.6125) -> (-28.375, 23.6125)
  line L3 (-28.375, 23.6125) -> (-28.375, -23.6125)
  dimension "d447" = 28.375
  dimension "d448" = 23.6125
  dimension "d449" = 28.375
  dimension "d450" = 23.6125
  constraint horizontal L0
  constraint vertical L1
  constraint horizontal L2
  constraint vertical L3
  measures "d447" horizontal distance of origin L0.start
  measures "d448" vertical distance of origin L0.start
  measures "d449" horizontal distance of origin L1.end
  measures "d450" vertical distance of origin L1.end
extrude "Panel" add sketch "Outline (8)" along normal blind 3.175 separate body makes body 24 in component "extra_door"
sketch "Outline (9)" plane through (0, 0, 0) normal (0, 0, 1) x (1, 0, 0) in component "extra_window"
  line L0 (-28.375, -18.85) -> (28.375, -18.85)
  line L1 (28.375, -18.85) -> (28.375, 18.85)
  line L2 (28.375, 18.85) -> (-28.375, 18.85)
  line L3 (-28.375, 18.85) -> (-28.375, -18.85)
  line L4 (-14.2875, -7.9375) -> (14.2875, -7.9375)
  line L5 (14.2875, -7.9375) -> (14.2875, 7.9375)
  line L6 (14.2875, 7.9375) -> (-14.2875, 7.9375)
  line L7 (-14.2875, 7.9375) -> (-14.2875, -7.9375)
  dimension "d458" = 28.375
  dimension "d459" = 18.85
  dimension "d460" = 28.375
  dimension "d461" = 18.85
  dimension "d462" = 14.2875
  dimension "d463" = 7.9375
  dimension "d464" = 14.2875
  dimension "d465" = 7.9375
  constraint horizontal L0
  constraint vertical L1
  constraint horizontal L2
  constraint vertical L3
  constraint horizontal L4
  constraint vertical L5
  constraint horizontal L6
  constraint vertical L7
  measures "d458" horizontal distance of origin L0.start
  measures "d459" vertical distance of origin L0.start
  measures "d460" horizontal distance of origin L1.end
  measures "d461" vertical distance of origin L1.end
  measures "d462" horizontal distance of origin L4.start
  measures "d463" vertical distance of origin L4.start
  measures "d464" horizontal distance of origin L5.end
  measures "d465" vertical distance of origin L5.end
extrude "Panel'" add sketch "Outline (9)" along normal blind 3.175 separate body makes body 25 in component "extra_window"
component "log_1insert_1-5_8" placed x (1, 0, 0) y (0, 1, 0) z (0, 0, 1) at (0, 245, 0)
component "log_1insert_1-1_2_round" placed x (1, 0, 0) y (0, 1, 0) z (0, 0, 1) at (60, 245, 0)
component "log_1insert_1-1_2_octagonal" placed x (1, 0, 0) y (0, 1, 0) z (0, 0, 1) at (120, 245, 0)
component "log_2insert_4-1_2" placed x (1, 0, 0) y (0, 1, 0) z (0, 0, 1) at (0, 175, 0)
component "log_2insert_6" placed x (1, 0, 0) y (0, 1, 0) z (0, 0, 1) at (0, 105, 0)
component "log_3insert_7-5_8" placed x (1, 0, 0) y (0, 1, 0) z (0, 0, 1) at (0, 35, 0)
component "log_4insert_10-5_8" placed x (1, 0, 0) y (0, 1, 0) z (0, 0, 1) at (0, 0, 0)
component "beveled_end_4-3_4" placed x (1, 0, 0) y (0, 1, 0) z (0, 0, 1) at (0, 140, 0)
component "half_log_4-1_2" placed x (1, 0, 0) y (0, 1, 0) z (0, 0, 1) at (0, 210, 0)
component "half_log_7-1_2" placed x (1, 0, 0) y (0, 1, 0) z (0, 0, 1) at (0, 70, 0)
component "beveled_end_1-1_2" placed x (1, 0, 0) y (0, 1, 0) z (0, 0, 1) at (180, 245, 0)
component "solid_log_1-3_8" placed x (1, 0, 0) y (0, 1, 0) z (0, 0, 1) at (10, 285, 0)
component "solid_log_1-5_8" placed x (1, 0, 0) y (0, 1, 0) z (0, 0, 1) at (50, 285, 0)
component "gable_plastic_8-1_2" placed x (1, 0, 0) y (0, 1, 0) z (0, 0, 1) at (320, 185, 0)
component "gable_plastic_small_2notch" placed x (1, 0, 0) y (0, 1, 0) z (0, 0, 1) at (320, 260, 0)
component "gable_wood_triangle_4x2" placed x (1, 0, 0) y (0, 1, 0) z (0, 0, 1) at (480, 260, 0)
component "shingle_flat_6" placed x (1, 0, 0) y (0, 1, 0) z (0, 0, 1) at (320, 70, 0)
component "shingle_flat_9" placed x (1, 0, 0) y (0, 1, 0) z (0, 0, 1) at (320, 35, 0)
component "shingle_flat_11" placed x (1, 0, 0) y (0, 1, 0) z (0, 0, 1) at (320, 0, 0)
component "shingle_ridge_5-5_8" placed x (1, 0, 0) y (0, 1, 0) z (0, 0, 1) at (480, 150, 0)
component "shingle_ridge_6" placed x (1, 0, 0) y (0, 1, 0) z (0, 0, 1) at (320, 150, 0)
component "shingle_ridge_9" placed x (1, 0, 0) y (0, 1, 0) z (0, 0, 1) at (320, 110, 0)
component "chimney" placed x (1, 0, 0) y (0, 1, 0) z (0, 0, 1) at (100, 290, 0)
component "extra_door" placed x (1, 0, 0) y (0, 1, 0) z (0, 0, 1) at (160, 300, 0)
component "extra_window" placed x (1, 0, 0) y (0, 1, 0) z (0, 0, 1) at (240, 300, 0)
equation "LogDia = 0.75 in" comment "Log diameter"
equation "NotchDepth = 0.1875 in" comment "Notch depth, each side of a log"
equation "NotchCenters = 3 in" comment "Spacing between notch centres"
equation "Clearance = 0.2 mm" comment "Fit clearance per side. Try 0.3 mm for PETG"
equation "NotchWidth = LogDia + 2 * Clearance" comment "Notch width (log diameter plus clearance)"
equation "PrintFlat = 0.8 mm" comment "Depth of the flat a round log lies on while printing"
equation "CourseRise = LogDia - 2 * NotchDepth" comment "Height gained per crossing course"
equation "HalfLogHeight = LogDia - NotchDepth" comment "Half-log height (flat sits at the notch floor)"
equation "GableThk = LogDia" comment "Gable thickness (fills a notch like a log)"
equation "ShingleThk = 0.125 in" comment "Shingle thickness"
equation "FlatShingleWidth = 0.8 in" comment "Flat shingle width"
equation "RidgeShingleWidth = 1.125 in" comment "Ridge shingle width"
equation "RidgeGrooveWidth = 1.6 mm" comment "Ridge shingle centre groove width"
equation "RidgeGrooveDepth = 0.8 mm" comment "Ridge shingle centre groove depth"
equation "PanelThk = 0.125 in" comment "Door and window panel thickness"
equation "L1a_Length = 1.625 in" comment "Overall length"
equation "L1a_Notches = 1" comment "Number of notch positions"
equation "L1a_FirstNotch = ( L1a_Length - ( L1a_Notches - 1 ) * NotchCenters ) / 2" comment "Centre of the first notch (keeps the row of notches centred)"
equation "L1a_NotchStep = NotchCenters * min(1; L1a_Notches - 1) + 0.001 mm * ( 1 - min(1; L1a_Notches - 1) )" comment "Pattern step: NotchCenters, or about zero when there is only one notch"
equation "d20 = LogDia / 2 - PrintFlat"
equation "d21 = LogDia"
equation "d22 = L1a_Length"
equation "d24 = L1a_FirstNotch - NotchWidth / 2"
equation "d25 = LogDia / 2 - NotchDepth"
equation "d26 = L1a_FirstNotch + NotchWidth / 2"
equation "d27 = LogDia / 2 + 1 mm"
equation "d28 = L1a_FirstNotch - NotchWidth / 2"
equation "d29 = LogDia / 2 - NotchDepth"